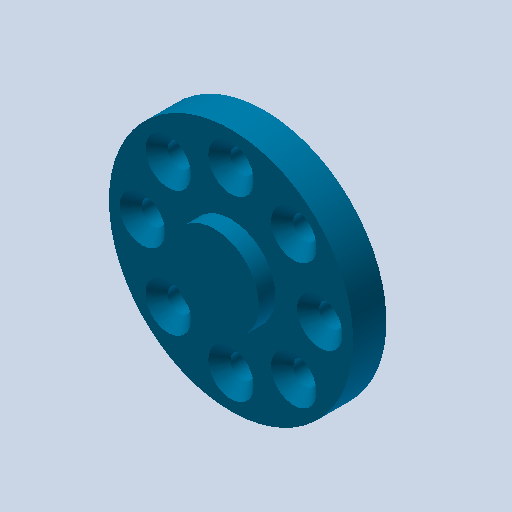
# Autodesk Inventor part: Bearing
Saved by Autodesk Inventor 2025.2 (Build 292293000, 293)
## iProperties
Created: 2010-02-24
Part Number: Bearing
Document SubType Name: Modeling
Designer: Administrator
Material: Generic
Density: 1 g/cm^3
Appearance: Sky Blue Medium
Mass: 1.2487 g
Surface Area: 11.6312 cm^2
Volume: 1.2487 cm^3
d0: 4.000 mm
d1: 11.000 mm
d2: 6.000 mm
d3: 3.000 mm
d5: 8.000 mm
d6: 2.100 mm
d13: 8.000 ul
d14: 360.00 deg
d16: 1.000 mm
d19: 8.000 mm
d20: 1.500 mm
d21: 0.00 deg
Author: Administrator
Autodesk Inventor part; units mm, degrees
ref_plane "YZ Plane" through (0, 0, 0) normal (1, 0, 0) x (0, 1, 0)
ref_plane "XZ Plane" through (0, 0, 0) normal (0, 1, 0) x (-1, 0, 0)
ref_plane "XY Plane" through (0, 0, 0) normal (0, 0, 1) x (1, 0, 0)
sketch "Sketch1" plane through (0, 0, 0) normal (0, 0, 1) x (1, 0, 0)
  line L0 (-0.3398, 3.9417) -> (-11.3398, 3.9417)
  line L1 (-11.3398, 3.9417) -> (-11.3398, 6.9417)
  line L2 (-11.3398, 6.9417) -> (-0.3398, 6.9417)
  line L3 (-0.3398, 6.9417) -> (-0.3398, 3.9417)
  line L4 (-0.3398, 3.9417) -> (-4.3398, 3.9417)
  line L5 (-4.3398, 3.9417) -> (-4.3398, 9.9417)
  line L6 (-4.3398, 9.9417) -> (-0.3398, 9.9417)
  line L7 (-0.3398, 9.9417) -> (-0.3398, 3.9417)
  dimension "d0" = 4
  dimension "d1" = 11
  dimension "d2" = 6
  dimension "d3" = 3
  constraints: 16 end point, 4 parallel, 2 horizontal, 2 perpendicular
  measures "d0" distance of L5.end L6.end
  measures "d1" distance of L1.end L2.end
  measures "d2" distance of L6.end L0.start
  measures "d3" distance of L0.end L1.end
revolve "迴轉1" add sketch "Sketch1" angle 360 about axis through (-0.3398, 6.9417, 0) along (0, -1, 0)
sketch "Sketch2" plane through (-0.3398, 3.9417, 0) normal (0, -1, 0) x (1, 0, 0)
  circle A0 centre (0, 0) radius 11 projected
  circle A1 centre (0, 0) radius 4
  point P0 (0, 8)
  dimension "d5" = 8
  dimension "d19" = 8
  constraints: 1 centre point, 1 coincident
  measures "d5" distance of point (0, 8) A0.centre
  measures "d19" diameter of A1
hole "孔1" at (-0.3398, 3.9417, 8) direction (0, 1, 0) diameter 2.1 end through all
pattern_circular "環形陣列1" count 8 over 360 about axis through (-0.3398, 5.4417, 0) along (0, 1, 0) of "孔1"
chamfer "去角1" distance 1 angle 45 8 edges at (-6.7391, 3.9417, -6.3993) (-0.3398, 3.9417, -9.05) (6.0595, 3.9417, -6.3993) (8.7102, 3.9417, 0) (6.0595, 3.9417, 6.3993) (-0.3398, 3.9417, 9.05) (-6.7391, 3.9417, 6.3993) (-9.3898, 3.9417, 0)
extrude "Extrusion1" add sketch "Sketch2" along normal blind 1.5 contours A1
body "Solid1"
